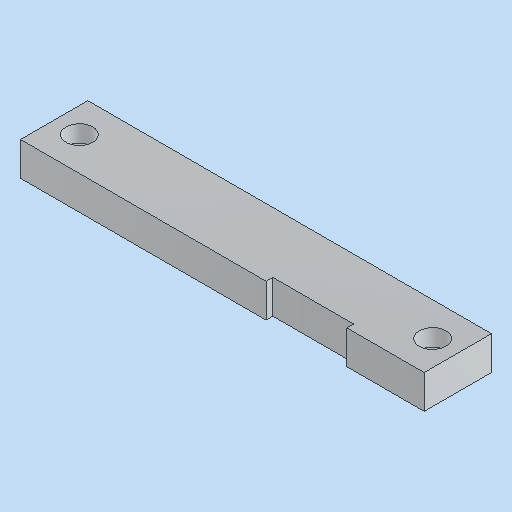
# Autodesk Inventor part: MM0937AN100_G16_154
Saved by Autodesk Inventor 2023.3 (Build 273359000, 359)
## iProperties
Created: 2024-03-15
Part Number: MM0937AN100_G16_154
Material: 3.3547 AlMg4,5Mn0,7 - AW 5083
Description: =<RBPARTNOTITLE2>
Document SubType Name: Modeling
Designer: FSM9BW
Mass: 60.8031 g
Surface Area: 78.7308 cm^2
Volume: 22.8583 cm^3
Density: 2.66 g/cm^3
Appearance: Aluminium AnP
RBPARTMADEOF: 10 x 20 x 120 (FM)
RBDRAWINGMISSINGSPEC: --
AnP_Kategorie: 1
RBPARTNOTITLE2: Anfertigungsteil
RBSURFACE: anodised colourless
RBPARTNOTITLE1: manufactured part
RBSURFACE2: eloxiert farblos
AnP_Material: =<Material>
RBMATERIAL: =<Material>
RBMATNO: =<Part Number>
RBPARTNO: SIEHE MNR
MaxAbmaße: 10 x 20 x 120 (FM)
Author: FSM9BW
Keywords: =<RBPARTMADEOF>
Comments: =<RBSURFACE2>
Revision Number: 01
Autodesk Inventor part; units mm, degrees
ref_plane "YZ Plane" through (0, 0, 0) normal (1, 0, 0) x (0, 1, 0)
ref_plane "XZ Plane" through (0, 0, 0) normal (0, 1, 0) x (-1, 0, 0)
ref_plane "XY Plane" through (0, 0, 0) normal (0, 0, 1) x (1, 0, 0)
sketch "Skizze1" plane through (0, 0, 0) normal (0, 0, 1) x (1, 0, 0)
  line L0 (-60, -10) -> (60, -10)
  line L1 (60, -10) -> (60, 10)
  line L2 (60, 10) -> (-60, 10)
  line L3 (-60, 10) -> (-60, -10)
  line L4 (0, -14) -> (0, 14) projected
  point P0 (0, 0)
  dimension "d0" = 120
  dimension "d1" = 20
  dimension "d2" = 10
  constraints: 8 end point, 2 parallel, 1 horizontal, 1 perpendicular, 1 other
  measures "d0" distance of L1.end L2.end
  measures "d1" distance of L2.end L0.start
  measures "d2" distance from line of L2 point (0, 0)
extrude "Extrusion1" add sketch "Skizze1" along normal blind 10
sketch "Skizze4" plane through (0, 0, 10) normal (0, 0, 1) x (1, 0, 0)
  point P0 (0, 0)
  point P1 (-52.5, 0)
  point P2 (52.5, 0)
  dimension "d16" = 52.5
  dimension "d17" = 52.5
  constraints: 2 horizontal alignment
  measures "d16" distance of point (-52.5, 0) point (0, 0)
  measures "d17" distance of point (0, 0) point (52.5, 0)
hole "Bohrung2" at (-52.5, 0, 10) at (52.5, 0, 10) direction (0, 0, -1) diameter 4.5 end through all counterbore diameter 8 counterbore depth 5
sketch "Skizze6" plane through (0, 0, 0) normal (0, 0, -1) x (-1, 0, 0)
  line L0 (-37, -10) -> (-13, -10)
  line L1 (-13, -10) -> (-13, -8)
  line L2 (-13, -8) -> (-37, -8)
  line L3 (-37, -8) -> (-37, -10)
  line L4 (-60, -10) -> (-60, 10) projected
  line L5 (60, -10) -> (-60, -10) projected
  point P0 (0, 0)
  dimension "d32" = 23
  dimension "d33" = 47
  dimension "d34" = 2
  constraints: 8 end point, 2 parallel, 1 collinear, 1 horizontal, 1 perpendicular
  measures "d32" distance between parallel lines of L4 L3
  measures "d33" distance between parallel lines of L1 L4
  measures "d34" distance of L2.end L0.start
extrude "Extrusion3" cut sketch "Skizze6" against normal through all
